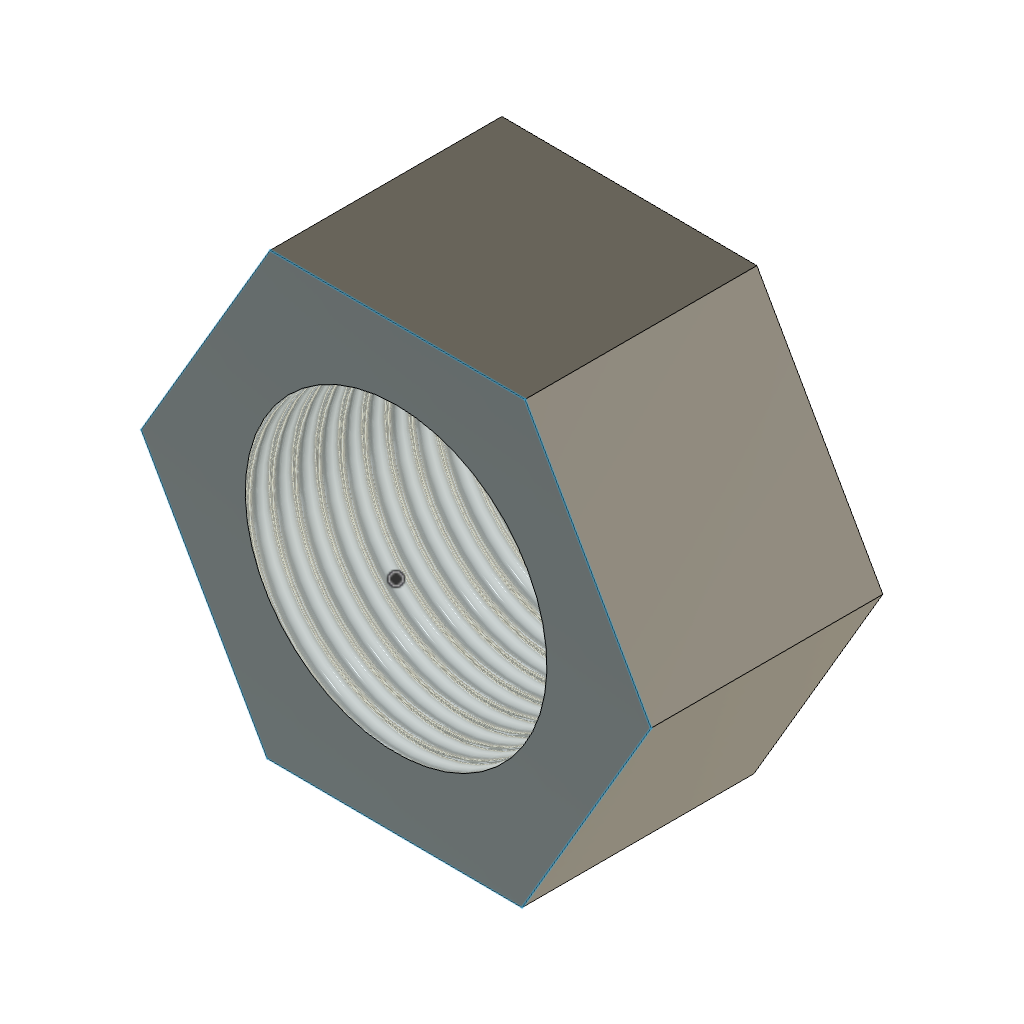
locknut (Autodesk Fusion 360 design; units mm, degrees)
part number: 2026-10-08-14-28-35-876
Autodesk Fusion 360 part; units mm, degrees
sketch "Sketch1" plane through (0, 0, 0) normal (0, 1, 0) x (1, 0, 0)
  line L0 (10.87, 19.127) -> (-11.1295, 18.9772)
  line L1 (-11.1295, 18.9772) -> (-21.9995, -0.1498)
  line L2 (-21.9995, -0.1498) -> (-10.87, -19.127)
  line L3 (-10.87, -19.127) -> (11.1295, -18.9772)
  line L4 (11.1295, -18.9772) -> (21.9995, 0.1498)
  line L5 (21.9995, 0.1498) -> (10.87, 19.127)
  dimension "d1" = 22
  measures "d1" distance of L0.start origin
extrude "Extrude1" add sketch "Sketch1" along normal blind 20
hole "Hole2" at (0, 0, 0) direction (0, 1, 0) diameter 26.022 depth 48 tip angle 118
thread "Thread2" "ISO Metric profile 28.0 M28x2 M28x2 6H" thread offset 0 thread depth 7.4
